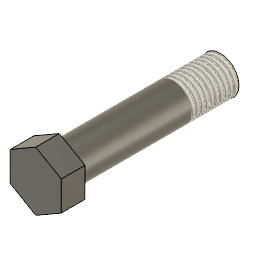
assembled (~recovered) (Autodesk Fusion 360 archive; units mm, degrees)
design "bolt"
part number: 2026-08-13-14-26-27-761
Autodesk Fusion 360 part; units mm, degrees
sketch "Sketch1" plane through (0, 0, 0) normal (0, 1, 0) x (1, 0, 0)
  line L0 (10.8253, -6.25) -> (10.8253, 6.25)
  line L1 (10.8253, 6.25) -> (0, 12.5)
  line L2 (0, 12.5) -> (-10.8253, 6.25)
  line L3 (-10.8253, 6.25) -> (-10.8253, -6.25)
  line L4 (-10.8253, -6.25) -> (0, -12.5)
  line L5 (0, -12.5) -> (10.8253, -6.25)
  circle A0 centre (0, 0) radius 8
  dimension "d1" = 12.5
  dimension "d2" = 16
  constraint coincident A0.centre origin
  measures "d1" distance of L0.start A0.centre
  measures "d2" diameter of A0
extrude "Extrude1" add sketch "Sketch1" along normal blind 10
sketch "Sketch2" plane through (0, 0, 0) normal (0, 1, 0) x (1, 0, 0)
  circle A0 centre (0, 0) radius 8
  dimension "d5" = 16
  constraint coincident A0.centre origin
  measures "d5" diameter of A0
extrude "Extrude2" add sketch "Sketch2" along normal blind 78
thread "Thread2" "ISO Metric profile 16.0 M16x2 M16x2 6g" major diameter 15.822 minor diameter 13.534 pitch 2 angle 60 resizes the face on face at (7.9901, 55.3333, 0.3988) from (0, 58, 0) to (0, 78, 0)
sketch "Sketch3" plane through (10.8253, 0, 0) normal (1, 0, 0) x (0, 1, 0)
  line L0 (0, 6.25) -> (0, -6.25)
  line L1 (0, -6.25) -> (10, -6.25)
  line L2 (10, -6.25) -> (10, 6.25)
  line L3 (10, 6.25) -> (0, 6.25)
thread "Thread1" [rolled back] thread offset 0 thread length 20

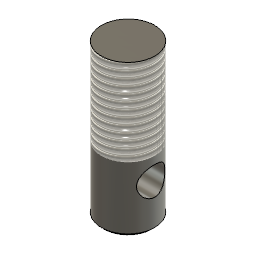
design "screw1"
part number: 2026-08-20-14-31-36-616
Autodesk Fusion 360 part; units mm, degrees
sketch "Sketch1" plane through (0, 0, 0) normal (0, 1, 0) x (1, 0, 0)
  circle A0 centre (0, 0) radius 10
  dimension "d1" = 20
  constraint coincident A0.centre origin
  measures "d1" diameter of A0
extrude "Extrude1" add sketch "Sketch1" along normal blind 56
sketch "Sketch2" plane through (0, 0, 0) normal (1, 0, 0) x (0, 0, -1)
  circle A0 centre (0, 16) radius 5.25
  dimension "d4" = 10.5
  dimension "d5" = 16
  measures "d4" diameter of A0
  measures "d5" distance of origin A0.centre
extrude "Extrude2" cut sketch "Sketch2" along normal mid plane 40
thread "Thread1" "ISO Metric profile 20.0 M20x2.5 M20x2.5 6g" major diameter 19.7905 minor diameter 16.938 pitch 2.5 angle 60 resizes the face on face at (7.7578, 24.0417, 6.31) from (0, 24, 0) to (0, 56, 0)
chamfer "Chamfer1" distance 1 angle 45 1 edges at (-9.2256, 0, 3.5783) tangent chain off

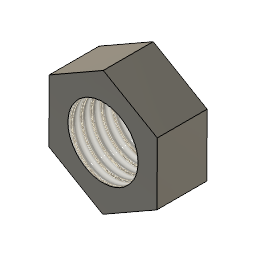
design "nut"
part number: 2026-08-20-13-22-31-592
Autodesk Fusion 360 part; units mm, degrees
sketch "Sketch1" plane through (0, 0, 0) normal (0, 1, 0) x (1, 0, 0)
  line L0 (10.853, -6.2017) -> (10.7974, 6.2981)
  line L1 (10.7974, 6.2981) -> (-0.0557, 12.4999)
  line L2 (-0.0557, 12.4999) -> (-10.853, 6.2017)
  line L3 (-10.853, 6.2017) -> (-10.7974, -6.2981)
  line L4 (-10.7974, -6.2981) -> (0.0557, -12.4999)
  line L5 (0.0557, -12.4999) -> (10.853, -6.2017)
  dimension "d1" = 12.5
  measures "d1" distance of L0.start origin
extrude "Extrude1" add sketch "Sketch1" along normal blind 10
sketch "Sketch2" plane through (0, 0, 0) normal (0, -1, 0) x (1, 0, 0)
  line L0 (10.853, 6.2017) -> (0.0557, 12.4999)
  line L1 (0.0557, 12.4999) -> (-10.7974, 6.2981)
  line L2 (-10.7974, 6.2981) -> (-10.853, -6.2017)
  line L3 (-10.853, -6.2017) -> (-0.0557, -12.4999)
  line L4 (-0.0557, -12.4999) -> (10.7974, -6.2981)
  line L5 (10.7974, -6.2981) -> (10.853, 6.2017)
  circle A0 centre (0, 0) radius 8
  dimension "d4" = 16
  constraint coincident A0.centre origin
  measures "d4" diameter of A0
extrude "Extrude2" cut sketch "Sketch2" against normal blind 44 contours A0
thread "Thread1" "ISO Metric profile 16.0 M16x2 M16x2 6H" major diameter 16.2505 minor diameter 14.0225 pitch 2 angle 60 resizes the face on face at (7.9602, 3.3333, -0.7965)

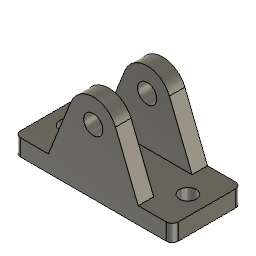
design "base"
part number: 2026-08-13-13-51-28-475
Autodesk Fusion 360 part; units mm, degrees
sketch "Sketch1" plane through (0, 0, 0) normal (0, 0, 1) x (1, 0, 0)
  line L0 (66, 29) -> (-66, 29)
  line L1 (-66, 29) -> (-66, -29)
  line L2 (-66, -29) -> (66, -29)
  line L3 (66, -29) -> (66, 29)
  line L4 (66, 29) -> (-66, -29) construction
  line L5 (-66, 29) -> (66, -29) construction
  circle A0 centre (-50, 0) radius 7
  circle A1 centre (50, 0) radius 7
  dimension "d1" = 132
  dimension "d2" = 58
  dimension "d3" = 14
  dimension "d4" = 14
  dimension "d5" = 16
  dimension "d6" = 16
  constraint horizontal L0
  constraint perpendicular L0 L1
  constraint parallel L0 L2
  constraint parallel L1 L3
  constraint coincident L4 origin
  constraint coincident L5 origin
  measures "d1" distance of L1.end L2.end
  measures "d2" distance of L0.end L1.end
  measures "d3" diameter of A0
  measures "d4" diameter of A1
  measures "d5" distance of L1 A0.centre
  measures "d6" distance of L3 A1.centre
extrude "Extrude1" add sketch "Sketch1" along normal blind 14
sketch "Sketch2" plane through (0, -29, 0) normal (0, -1, 0) x (1, 0, 0)
  line L0 (-66, 0) -> (66, 0)
  line L1 (66, 0) -> (66, 14)
  line L2 (66, 14) -> (-66, 14)
  line L3 (-66, 14) -> (-66, 0)
  line L4 (0, 14) -> (37.5, 14)
  line L5 (0, 14) -> (-37.5, 14)
  line L6 (0, 46) -> (0, 54)
  circle A0 centre (0, 54) radius 8
  line L7 (-18.575, 61.4141) -> (-37.5, 14)
  line L8 (37.5, 14) -> (18.575, 61.4141)
  arc A1 (18.575, 61.4141) -> (-18.575, 61.4141) centre (0, 54) ccw
  dimension "d9" = 37.5
  dimension "d10" = 37.5
  dimension "d11" = 40
  dimension "d12" = 16
  dimension "d13" = 40
  constraint midpoint L2 L4.start
  constraint parallel L2 L4
  constraint parallel L2 L5
  constraint perpendicular L2 L6
  constraint coincident L6.end A0.centre
  constraint concentric A0 A1
  constraint tangent L7 A1
  constraint tangent L8 A1
  constraint coincident A0 L6.start
  measures "d9" distance of L4.start L4.end
  measures "d10" distance of L4.start L5.end
  measures "d11" distance of L4.start L6.end
  measures "d12" diameter of A0
  measures "d13" diameter of A1
extrude "Extrude2" add sketch "Sketch2" against normal blind 58 contours L2 L4 L5 L7 L8 A1
sketch "Sketch3" plane through (0, 0, 0) normal (0, 0, -1) x (1, 0, 0)
  circle A0 centre (50, 0) radius 7
  circle A1 centre (-50, 0) radius 7
  line L0 (66, -29) -> (66, 29)
  line L1 (66, 29) -> (-66, 29)
  line L2 (-66, 29) -> (-66, -29)
  line L3 (-66, -29) -> (66, -29)
  line L4 (-37.5, 16) -> (37.5, 16)
  line L5 (37.5, 16) -> (37.5, -16)
  line L6 (37.5, -16) -> (-37.5, -16)
  line L7 (-37.5, -16) -> (-37.5, 16)
  line L8 (-37.5, 16) -> (37.5, -16) construction
  line L9 (37.5, 16) -> (-37.5, -16) construction
  dimension "d16" = 75
  dimension "d17" = 32
  constraint horizontal L4
  constraint perpendicular L4 L5
  constraint parallel L4 L6
  constraint parallel L5 L7
  constraint coincident L8 origin
  constraint coincident L9 origin
  measures "d16" distance of L5.end L6.end
  measures "d17" distance of L4.end L5.end
sketch "Sketch4" plane through (37.1668, 0, 14.8348) normal (0.928751, 0, 0.370704) x (0, 1, 0)
  line L0 (-29, 50.1526) -> (-29, -0.8989)
  line L1 (-29, -0.8989) -> (29, -0.8989)
  line L2 (29, -0.8989) -> (29, 50.1526)
  line L3 (29, 50.1526) -> (-29, 50.1526)
extrude "Extrude3" cut sketch "Sketch3" against normal blind 100 contours L4 L5 L6 L7
extrude "Extrude4" add 1 faces at (37.5, -5.3333, 9.3333) along direction (-1, 0, 0) blind 75
fillet "Fillet1" radius 5 1 edges at (66, 29, 7)
fillet "Fillet2" radius 5 1 edges at (66, -29, 7)
fillet "Fillet3" radius 5 1 edges at (-66, -29, 7)
fillet "Fillet4" radius 5 1 edges at (-66, 29, 7)

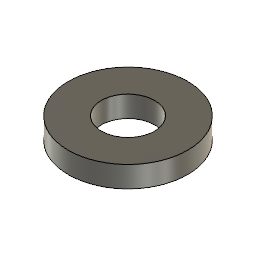
design "lock nut"
part number: 2026-08-20-13-42-43-430
Autodesk Fusion 360 part; units mm, degrees
sketch "Sketch1" plane through (0, 0, 0) normal (0, 0, 1) x (1, 0, 0)
  circle A0 centre (0, 0) radius 22.5
  circle A1 centre (0, 0) radius 10
  dimension "d1" = 45
  dimension "d2" = 20
  constraint coincident A0.centre A1.centre
  measures "d1" diameter of A0
  measures "d2" diameter of A1
extrude "Extrude1" add sketch "Sketch1" along normal blind 8

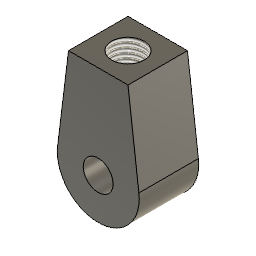
design "swival"
part number: 2026-08-20-13-28-36-642
Autodesk Fusion 360 part; units mm, degrees
sketch "Sketch1" plane through (0, 0, 0) normal (0, 1, 0) x (1, 0, 0)
  line L0 (0, 0) -> (0, -50)
  line L1 (0, -50) -> (16, -50)
  line L2 (0, -50) -> (-16, -50)
  line L3 (-16, -50) -> (-21.8346, -2.6929)
  line L4 (16, -50) -> (21.8346, -2.6929)
  circle A0 centre (0, 0) radius 8
  arc A1 (21.8346, -2.6929) -> (-21.8346, -2.6929) centre (0, 0) ccw
  dimension "d2" = 50
  dimension "d3" = 16
  dimension "d4" = 16
  dimension "d5" = 44
  dimension "d6" = 16
  constraint vertical L0
  constraint perpendicular L0 L1
  constraint perpendicular L0 L2
  constraint coincident L0.start A0.centre
  constraint tangent L4 A1
  constraint tangent L3 A1
  measures "d2" distance of L0.start L0.end
  measures "d3" distance of L0.end L1.end
  measures "d4" distance of L0.end L2.end
  measures "d5" diameter of A1
  measures "d6" diameter of A0
extrude "Extrude1" add sketch "Sketch1" along normal blind 32
hole "Hole1" at (0, 16, 50) direction (0, 0, -1) diameter 17.519 depth 32 tip angle 118
thread "Thread1" "ISO Metric profile 20.0 M20x2.5 M20x2.5 6H" thread offset 0 thread depth 7.4
